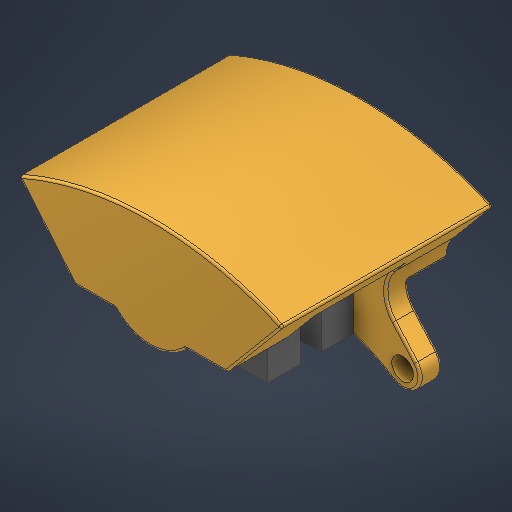
# Autodesk Inventor part: Dynapro_120_9689_LP_Rough_CAD
Saved by Autodesk Inventor 2026.1 (Build 301233000, 233)
## iProperties
Created: 2026-10-11
Part Number: Dynapro_120_9689_LP_Rough_CAD
Material: Generic
Document SubType Name: Modeling
Designer: share
Density: 1 g/cm^3
Appearance: Default
Author: share
Autodesk Inventor part; units mm, degrees
ref_plane "YZ Plane" through (0, 0, 0) normal (1, 0, 0) x (0, 1, 0)
ref_plane "Work Plane1" through (0, 0, -48.5) normal (0, 0, 1) x (1, 0, 0)
sketch "Sketch1" plane through (0, 0, -48.5) normal (0, 0, 1) x (1, 0, 0)
  line L0 (0, 207.62) -> (0, -207.62) construction
  line L1 (-207.62, 0) -> (207.62, 0) construction
  circle A0 centre (0, 0) radius 91.7 construction
  circle A1 centre (0, 0) radius 148.3 construction
  arc A2 (60.7, 135.3085) -> (-60.7, 135.3085) centre (0, 0) ccw
  line L2 (-60.7, 135.3085) -> (-35, 104.6571)
  line L3 (60.7, 135.3085) -> (35, 104.6571)
  line L4 (-35, 104.6571) -> (35, 104.6571) construction
  arc A3 (-16.3997, 104.6571) -> (16.3997, 104.6571) centre (0, 119.6571) ccw
  line L5 (-35, 104.6571) -> (-16.3997, 104.6571)
  line L6 (16.3997, 104.6571) -> (35, 104.6571)
  point P0 (-47.625, 78.3629)
  point P1 (47.625, 78.3629)
  dimension "d0" = 183.4
  dimension "d1" = 296.6
  dimension "d3" = 95.25
  dimension "d8" = 121.4
  dimension "d9" = 40
  dimension "d10" = 70
  dimension "d11" = 44.45
  dimension "d12" = 15
  constraints: 10 end point, 4 point on circle, 3 point on line, 3 symmetric about line, 2 centre point, 2 coincident, 1 collinear, 1 horizontal, 7 other
  measures "d3" distance of point (47.625, 78.363) point (-47.625, 78.363)
  measures "d8" distance of L3.start L2.start
  measures "d9" distance of L2.start L2.end
  measures "d10" distance of L3.end L2.end
  measures "d11" diameter of A3
  measures "d12" distance from line of A3.centre L4
ref_plane "Work Plane2" through (0, 0, 48.5) normal (0, 0, 1) x (1, 0, 0)
extrude "Extrusion1" add sketch "Sketch1" along normal up to surface (97 mm away)
sketch "Sketch2" plane through (0, 0, 0) normal (0, 0, 1) x (1, 0, 0)
  circle A0 centre (0, 0) radius 128.5
  circle A1 centre (0, 0) radius 148.3 construction
  dimension "d18" = 19.8
  constraints: 1 centre point, 1 coincident
  measures "d18" radial gap between concentric circles of A0 A1
extrude "Extrusion2" cut sketch "Sketch2" along normal mid plane 39.6
sketch "Sketch3" plane through (0, 0, -19.8) normal (0, 0, 1) x (1, 0, 0)
  arc A0 (60.7, 135.3085) -> (-60.7, 135.3085) centre (0, 0) ccw projected
  line L0 (-35, 104.6571) -> (-60.7, 135.3085) projected
  line L1 (-16.3997, 104.6571) -> (-35, 104.6571) projected
  arc A1 (-16.3997, 104.6571) -> (16.3997, 104.6571) centre (0, 119.6571) ccw projected
  line L2 (35, 104.6571) -> (16.3997, 104.6571) projected
  line L3 (60.7, 135.3085) -> (35, 104.6571) projected
  circle A2 centre (0, 0) radius 91.7 construction
  circle A3 centre (-47.625, 78.3629) radius 8
  circle A4 centre (47.625, 78.3629) radius 8
  line L4 (-35, 104.6571) -> (-53.6105, 83.6708)
  line L5 (35, 104.6571) -> (53.6105, 83.6708)
  arc A5 (43.2955, 71.6357) -> (-43.2955, 71.6357) centre (0, 4.3639) ccw
  dimension "d21" = 16
  dimension "d22" = 80
  constraints: 6 point on circle, 4 end point, 4 tangent, 3 centre point, 2 coincident, 1 equal radius
  measures "d21" diameter of A3
  measures "d22" radius of A5
extrude "Extrusion3" add sketch "Sketch3" against normal blind 10 contours L5 A4 A5 A3 L4 L1 A1 L2 | A4 | A3
sketch "Sketch4" plane through (0, 0, -19.8) normal (0, 0, 1) x (1, 0, 0)
  point P0 (0, 0)
  point P1 (-47.625, 78.3629)
  point P2 (47.625, 78.3629)
hole "Hole1" at (-47.625, 78.3629, -19.8) at (47.625, 78.3629, -19.8) direction (0, 0, -1) diameter 10 end through all
fillet "Fillet1" radius 15 2 edges at (-35, 104.6571, -24.8) (35, 104.6571, -24.8)
fillet "Fillet2" radius 1 50 edges at (-60.7, 135.3085, 0) (0, 148.3, 48.5) (-47.85, 119.9828, 48.5) (-40.6624, 109.93, -48.5) (-52.0054, 124.9388, -48.5) (0, 148.3, -48.5) (40.6624, 109.93, -48.5) (52.0054, 124.9388, -48.5) (60.7, 135.3085, 0) (-47.395, 119.4402, 0) (-39.8076, 104.6571, -39.15) (-48.5964, 89.325, -29.8) (-53.6992, 73.1568, -29.8) (0, 84.3639, -29.8) (53.6992, 73.1568, -29.8) (48.5964, 89.325, -29.8) (40.8304, 99.481, -29.8) (-40.8304, 99.481, -29.8) (-53.6992, 73.1568, -19.8) (0, 84.3639, -19.8) (53.6992, 73.1568, -19.8) (48.5964, 89.325, -19.8) (39.8065, 104.7237, -19.8) (45.3529, 117.0046, -19.8) (-39.8065, 104.7237, -19.8) (-45.3529, 117.0046, -19.8) (-48.5964, 89.325, -19.8) (47.395, 119.4402, 0) (41.1975, 112.0487, 19.8) (-25.6999, 104.6571, 19.8) (0, 97.4321, 19.8) (25.6999, 104.6571, 19.8) (16.3997, 104.6571, 34.15) (-16.3997, 104.6571, 34.15) (-35, 104.6571, 34.15) (-41.1975, 112.0487, 19.8) (35, 104.6571, 34.15) (25.6999, 104.6571, 48.5) (47.85, 119.9828, 48.5) (-25.6999, 104.6571, 48.5) (0, 97.4321, 48.5) (28.1036, 104.6571, -29.8) (16.3997, 104.6571, -39.15) (0, 97.4321, -29.8) (-28.1036, 104.6571, -29.8) (-28.1036, 104.6571, -48.5) (0, 97.4321, -48.5) (28.1036, 104.6571, -48.5) (39.8076, 104.6571, -39.15) (-16.3997, 104.6571, -39.15)
sketch "Sketch5" plane through (0, 0, -19.8) normal (0, 0, 1) x (1, 0, 0)
  line L0 (-84.1119, 0) -> (84.1119, 0) construction
  line L1 (0, 177.96) -> (0, -29.66) construction
  line L2 (-25.15, 127.1629) -> (25.15, 127.1629)
  line L3 (25.15, 127.1629) -> (25.15, 81.1629)
  line L4 (25.15, 81.1629) -> (-25.15, 81.1629)
  line L5 (-25.15, 81.1629) -> (-25.15, 127.1629)
  circle A0 centre (-47.625, 78.3629) radius 5 projected
  circle A1 centre (47.625, 78.3629) radius 5 projected
  line L6 (-47.625, 78.3629) -> (47.625, 78.3629) construction
  point P0 (0, 0)
  dimension "d34" = 46
  dimension "d35" = 50.3
  dimension "d43" = 48.8
  constraints: 10 end point, 2 horizontal, 2 parallel, 1 perpendicular, 1 other
  measures "d34" distance between parallel lines of L4 L2
  measures "d35" distance between parallel lines of L3 L5
  measures "d43" distance between parallel lines of L6 L2
extrude "Extrusion4" add sketch "Sketch5" along normal blind 15 contours L2 L3 L4 L5
sketch "Sketch6" plane through (0, 0, 19.8) normal (0, 0, -1) x (-1, 0, 0)
  arc A0 (25.15, 126.0148) -> (18.4889, 127.1629) centre (0, 0) ccw projected
  line L0 (25.15, 126.0148) -> (25.15, 81.1629) projected
  line L1 (25.15, 81.1629) -> (-25.15, 81.1629) projected
  line L2 (-25.15, 81.1629) -> (-25.15, 126.0148) projected
  arc A1 (-18.4889, 127.1629) -> (-25.15, 126.0148) centre (0, 0) ccw projected
  line L3 (-18.4889, 127.1629) -> (18.4889, 127.1629) projected
extrude "Extrusion5" add sketch "Sketch6" along normal blind 15
body "Solid1"
